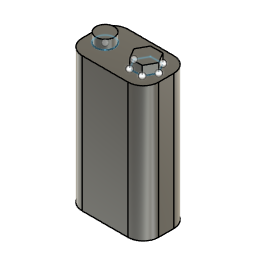
9V电池 v1 (Autodesk Fusion 360 design; units mm, degrees)
Autodesk Fusion 360 part; units mm, degrees
sketch "草图1" plane through (0, 0, 0) normal (0, 0, 1) x (1, 0, 0)
  line L0 (-7.5, 7.5) -> (7.5, 7.5)
  line L1 (12.5, 2.5) -> (12.5, -2.5)
  line L2 (7.5, -7.5) -> (-7.5, -7.5)
  line L3 (-12.5, -2.5) -> (-12.5, 2.5)
  line L4 (-20, 0) -> (35, 0) construction
  line L5 (0, -15) -> (0, 25) construction
  arc A0 (-7.5, 7.5) -> (-12.5, 2.5) centre (-7.5, 2.5) ccw
  arc A1 (12.5, 2.5) -> (7.5, 7.5) centre (7.5, 2.5) ccw
  arc A2 (-12.5, -2.5) -> (-7.5, -7.5) centre (-7.5, -2.5) ccw
  arc A3 (7.5, -7.5) -> (12.5, -2.5) centre (7.5, -2.5) ccw
  point P0 (12.5, 7.5)
  point P1 (12.5, -7.5)
  point P2 (-12.5, -7.5)
  dimension "d1" = 25
  dimension "d2" = 15
  dimension "d3" = 5
  dimension "d4" = 5
  dimension "d5" = 5
  dimension "d6" = 5
  constraint horizontal L0
  constraint vertical L1
  constraint horizontal L2
  constraint vertical L3
  constraint horizontal L4
  constraint vertical L5
  constraint symmetric L1 L3 L5
  constraint symmetric L0 L2 L4
  constraint tangent L3 A0
  constraint tangent L0 A0
  constraint coincident P0 L0
  constraint coincident P0 L1
  constraint tangent L0 A1
  constraint tangent L1 A1
  constraint coincident P2 L3
  constraint coincident P2 L2
  constraint tangent L3 A2
  constraint tangent L2 A2
  constraint coincident P1 L2
  constraint coincident P1 L1
  constraint tangent L2 A3
  constraint tangent L1 A3
  measures "d1" distance of P1 P2
  measures "d2" distance of P0 P1
  measures "d3" radius of A0
  measures "d4" radius of A1
  measures "d5" radius of A2
  measures "d6" radius of A3
extrude "拉伸1" add sketch "草图1" against normal blind 44 makes body 1
sketch "草图3" plane through (0, 0, 0) normal (0, 0, 1) x (1, 0, 0)
  circle A0 centre (-7.5, 0) radius 3
  line L0 (3.9367, 3.4268) -> (2.0007, -0.0735)
  line L1 (4.064, -3.5003) -> (2.0007, -0.0735)
  line L2 (4.064, -3.5003) -> (8.0633, -3.4268)
  line L3 (8.0633, -3.4268) -> (9.9993, 0.0735)
  line L4 (9.9993, 0.0735) -> (7.936, 3.5003)
  line L5 (7.936, 3.5003) -> (3.9367, 3.4268)
  dimension "d9" = 6
  measures "d9" diameter of A0
extrude "拉伸2" add sketch "草图3" along normal blind 3 separate body contours A0 makes body 2
extrude "拉伸3" add sketch "草图3" along normal blind 3 separate body contours L0 L1 L2 L3 L4 L5 makes body 3
